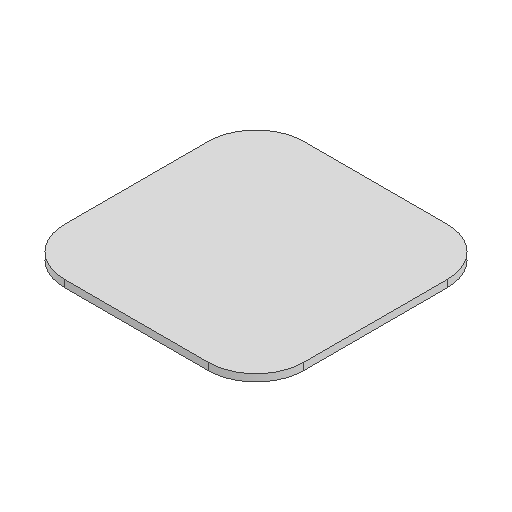
# Autodesk Inventor part: Quadrato
Saved by Autodesk Inventor 2025.4 (Build 294407000, 407)
## iProperties
Created: 2026-10-20
Part Number: Quadrato
Material: Generic
Document SubType Name: Modeling
Designer: gdira
Density: 1 g/cm^3
Appearance: Default
Author: gdira
Autodesk Inventor part; units mm, degrees
ref_plane "YZ Plane" through (0, 0, 0) normal (1, 0, 0) x (0, 1, 0)
ref_plane "XZ Plane" through (0, 0, 0) normal (0, 1, 0) x (-1, 0, 0)
ref_plane "XY Plane" through (0, 0, 0) normal (0, 0, 1) x (1, 0, 0)
sketch "Sketch1" plane through (0, 0, 0) normal (0, 1, 0) x (-1, 0, 0)
  line L0 (0, 1) -> (0, 4)
  line L1 (1, 5) -> (4, 5)
  line L2 (5, 4) -> (5, 1)
  line L3 (4, 0) -> (1, 0)
  arc A0 (5, 4) -> (4, 5) centre (4, 4) ccw
  arc A1 (4, 0) -> (5, 1) centre (4, 1) ccw
  arc A2 (0, 1) -> (1, 0) centre (1, 1) ccw
  arc A3 (1, 5) -> (0, 4) centre (1, 4) ccw
  point P0 (0, 0)
  point P1 (0, 5)
  point P2 (5, 5)
  dimension "d0" = 5
  dimension "d1" = 5
  dimension "d2" = 1
  constraints: 8 end point, 8 point on circle, 8 tangent, 6 point on line, 4 centre point, 3 equal radius, 2 parallel, 1 perpendicular, 1 vertical
  measures "d0" distance of point (0, 0) point (0, 5)
  measures "d1" distance of point (0, 5) point (5, 5)
  measures "d2" radius of A0
extrude "Extrusion1" add sketch "Sketch1" along normal blind 0.15
body "Solid1"
